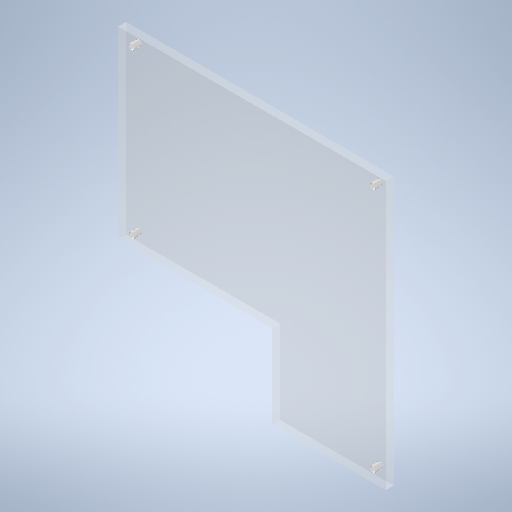
# Autodesk Inventor part: acrylic_cover_2
Saved by Autodesk Inventor 2025.1 (Build 291241000, 241)
## iProperties
Created: 2026-10-19
Part Number: acrylic_cover_2
Material: Generic
Document SubType Name: Modeling
Designer: Aiden Shaevitz
Density: 1 g/cm^3
Appearance: Default
Author: Aiden Shaevitz
Autodesk Inventor part; units mm, degrees
ref_plane "YZ Plane" through (0, 0, 0) normal (1, 0, 0) x (0, 1, 0)
ref_plane "XZ Plane" through (0, 0, 0) normal (0, 1, 0) x (-1, 0, 0)
ref_plane "XY Plane" through (0, 0, 0) normal (0, 0, 1) x (1, 0, 0)
sketch "Sketch1" plane through (0, 0, 0) normal (0, 0, 1) x (1, 0, 0)
  circle A0 centre (190.1189, 22.575) radius 3.302 projected
  circle A1 centre (-2.8811, 84.975) radius 3.302 projected
  circle A2 centre (271.9189, 260.375) radius 3.302 projected
  circle A3 centre (271.9189, -11.425) radius 3.302 projected
  circle A4 centre (-2.8811, 227.375) radius 3.302 projected
  circle A5 centre (271.9189, 227.375) radius 3.302 projected
  circle A6 centre (271.9189, 124.975) radius 3.302 projected
  circle A7 centre (-2.8811, 124.975) radius 3.302 projected
  circle A8 centre (-2.8811, 22.575) radius 3.302 projected
  circle A9 centre (271.9189, 22.575) radius 3.302 projected
  line L0 (-17.8811, 277.375) -> (-17.8811, -27.425) projected
  line L1 (-17.8811, -27.425) -> (286.9189, -27.425) projected
  line L2 (286.9189, -27.425) -> (286.9189, 277.375) projected
  line L3 (286.9189, 277.375) -> (-17.8811, 277.375) projected
  line L4 (-17.8811, -27.425) -> (286.9189, -27.425)
  line L5 (286.9189, -27.425) -> (286.9189, 277.375)
  line L6 (286.9189, 277.375) -> (-17.8811, 277.375)
  line L7 (-17.8811, 277.375) -> (-17.8811, -27.425)
  circle A10 centre (-2.8811, 260.3117) radius 3.302 projected
  circle A11 centre (-2.8811, 260.3117) radius 3.302 projected
  constraints: 8 end point, 2 parallel, 1 horizontal, 1 perpendicular
extrude "Extrusion1" add sketch "Sketch1" along normal blind 9 contours A0 | A1 | A2 | A3 | A4 | A5 | A6 | A7 | A8 | A9 | L3 L2 L1 L0 | A10
sketch "Sketch3" plane through (0, 0, 9) normal (0, 0, 1) x (1, 0, 0)
  line L0 (-17.8811, 277.375) -> (-17.8811, -27.425) projected
  line L1 (-17.8811, -27.425) -> (286.9189, -27.425) projected
  line L2 (286.9189, -27.425) -> (286.9189, 277.375) projected
  line L3 (286.9189, 277.375) -> (-17.8811, 277.375) projected
  circle A0 centre (271.9189, -14.525) radius 3.3
  circle A1 centre (271.9189, 264.475) radius 3.3
  circle A2 centre (-2.8811, 78.475) radius 3.3
  circle A3 centre (-2.8811, 264.475) radius 3.3
  point P0 (0, 0)
  constraints: 4 centre point, 8 other
hole "Hole1" at (271.9189, -14.525, 9) at (-2.8811, 78.475, 9) at (-2.8811, 264.475, 9) at (271.9189, 264.475, 9) direction (0, 0, -1) diameter 6.6 end through all
sketch "Sketch2" plane through (0, 0, 9) normal (0, 0, 1) x (1, 0, 0)
  line L0 (152.4955, 40.075) -> (134.9955, 40.075) projected
  line L1 (134.9955, 67.575) -> (134.9955, 40.075) projected
  line L2 (152.4955, 67.575) -> (134.9955, 67.575) projected
  line L3 (152.4955, 40.075) -> (152.4955, 67.575) projected
  line L4 (0, 67.575) -> (105, 67.575) projected
  line L5 (152.4955, 45.15) -> (152.4955, 0) projected
  line L6 (-17.8811, 277.375) -> (-17.8811, -27.425) projected
  line L7 (-17.8811, -27.425) -> (157.4955, -27.425)
  line L8 (157.4955, -27.425) -> (157.4955, 67.575)
  line L9 (157.4955, 67.575) -> (-17.8811, 67.575)
  line L10 (-17.8811, 67.575) -> (-17.8811, -27.425)
  point P0 (0, 0)
  point P1 (152.4955, 22.575)
  point P2 (-17.8811, 67.575)
  dimension "d2" = 5
  constraints: 8 end point, 2 parallel, 1 horizontal, 1 midpoint, 1 perpendicular, 1 point on line
  measures "d2" distance from line of point (152.496, 22.575) L8
extrude "Extrusion2" cut sketch "Sketch2" against normal through all
body "Solid1"
